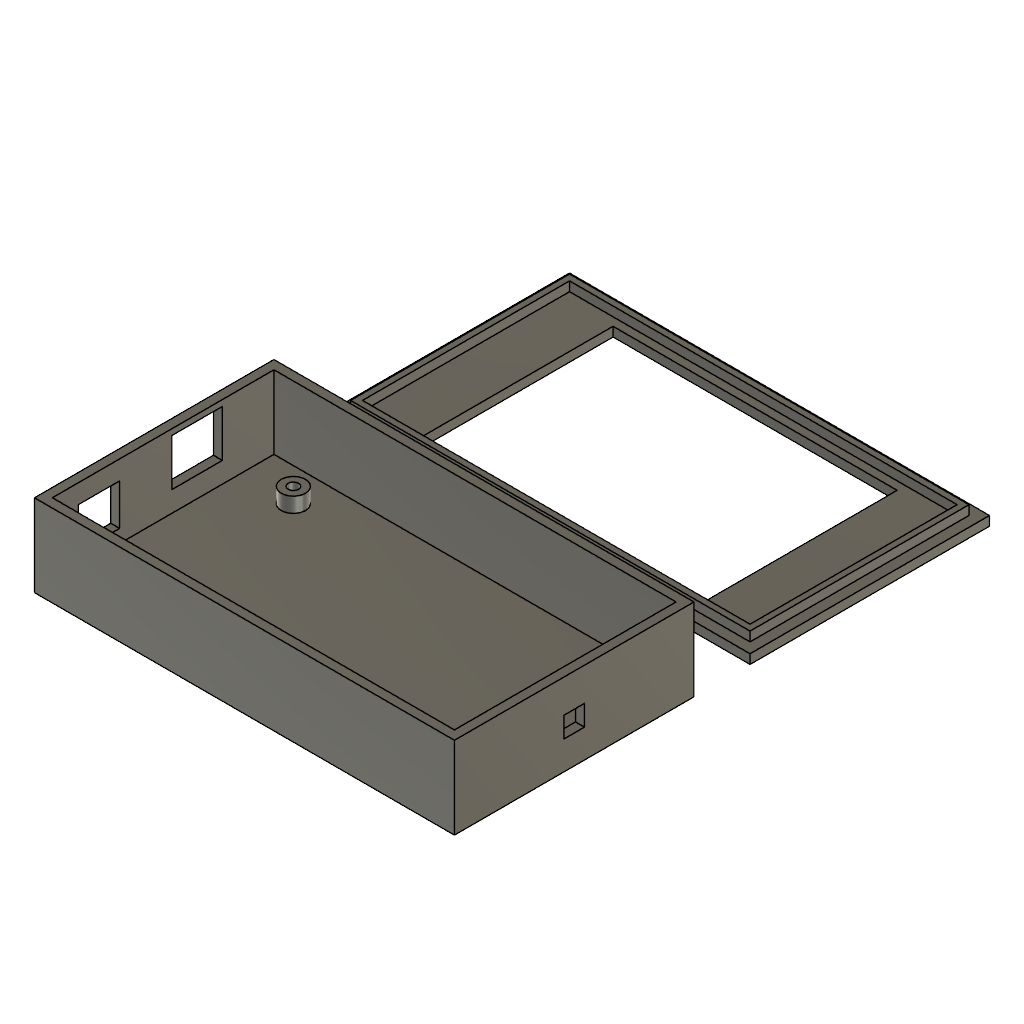
Caja Ardunino Mega (Autodesk Fusion 360 archive; units mm, degrees)
design "Caja Ardunino Mega"
part number: 2026-11-01-23-11-25-753
Autodesk Fusion 360 part; units mm, degrees
sketch "Boceto1" plane through (0, 0, 0) normal (0, 0, 1) x (1, 0, 0)
  line L0 (0, 0) -> (112.4, 0)
  line L1 (112.4, 0) -> (112.4, 64.1)
  line L2 (112.4, 64.1) -> (0, 64.1)
  line L3 (0, 64.1) -> (0, 0)
sketch "Boceto2" plane through (0, 0, 0) normal (0, 0, 1) x (1, 0, 0)
  circle A0 centre (16.4, 4.9) radius 3.25
  circle A1 centre (16.4, 52.9) radius 3.25
  circle A2 centre (97.4, 9.9) radius 3.25
  circle A3 centre (98.9, 37.9) radius 3.25
sketch "Boceto3" plane through (0, 0, 0) normal (0, 0, 1) x (1, 0, 0)
  circle A0 centre (16.4, 4.9) radius 1.4
  circle A1 centre (16.4, 52.9) radius 1.4
  circle A2 centre (97.4, 9.9) radius 1.4
  circle A3 centre (98.9, 37.9) radius 1.4
sketch "Boceto4" plane through (0, 0, 0) normal (1, 0, 0) x (0, 0, -1)
sketch "Boceto5" plane through (0, 0, 0) normal (0, 0, 1) x (1, 0, 0)
  line L0 (0, 0) -> (112.4, 0)
  line L1 (112.4, 0) -> (112.4, 64.1)
  line L2 (112.4, 64.1) -> (0, 64.1)
  line L3 (0, 64.1) -> (0, 0)
sketch "Boceto6" plane through (0, 0, 0) normal (0, 0, 1) x (1, 0, 0)
  circle A0 centre (16.4, 4.9) radius 3.25
  circle A1 centre (16.4, 52.9) radius 3.25
  circle A2 centre (97.4, 9.9) radius 3.25
  circle A3 centre (98.9, 37.9) radius 3.25
sketch "Boceto7" plane through (0, 0, 0) normal (0, 0, 1) x (1, 0, 0)
  circle A0 centre (16.4, 4.9) radius 1.4
  circle A1 centre (16.4, 52.9) radius 1.4
  circle A2 centre (97.4, 9.9) radius 1.4
  circle A3 centre (98.9, 37.9) radius 1.4
sketch "Boceto8" plane through (0, 0, 0) normal (1, 0, 0) x (0, 0, -1)
sketch "Boceto9" plane through (0, 0, 0) normal (0, 0, 1) x (1, 0, 0)
  line L0 (0, 0) -> (112.4, 0)
  line L1 (112.4, 0) -> (112.4, 64.1)
  line L2 (112.4, 64.1) -> (0, 64.1)
  line L3 (0, 64.1) -> (0, 0)
sketch "Boceto10" plane through (0, 0, 0) normal (0, 0, 1) x (1, 0, 0)
  line L0 (2.4, 2.4) -> (110, 2.4)
  line L1 (110, 2.4) -> (110, 61.7)
  line L2 (110, 61.7) -> (2.4, 61.7)
  line L3 (2.4, 61.7) -> (2.4, 2.4)
sketch "Boceto11" plane through (0, 0, 0) normal (0, 0, 1) x (1, 0, 0)
  circle A0 centre (16.4, 4.9) radius 3.25
  circle A1 centre (16.4, 52.9) radius 3.25
  circle A2 centre (97.4, 9.9) radius 3.25
  circle A3 centre (98.9, 37.9) radius 3.25
sketch "Boceto12" plane through (0, 0, 0) normal (0, 0, 1) x (1, 0, 0)
  circle A0 centre (16.4, 4.9) radius 1.4
  circle A1 centre (16.4, 52.9) radius 1.4
  circle A2 centre (97.4, 9.9) radius 1.4
  circle A3 centre (98.9, 37.9) radius 1.4
ref_plane "PlanoDeObra1" through (0, 0, 0) normal (1, 0, 0) x (0, 1, 0)
sketch "Boceto13" plane through (0, 0, 0) normal (1, 0, 0) x (0, 0, -1)
sketch "Boceto14" plane through (0, 0, 0) normal (0, 0, 1) x (1, 0, 0)
  line L0 (0, 0) -> (112.4, 0)
  line L1 (112.4, 0) -> (112.4, 64.1)
  line L2 (112.4, 64.1) -> (0, 64.1)
  line L3 (0, 64.1) -> (0, 0)
sketch "Boceto15" plane through (0, 0, 0) normal (0, 0, 1) x (1, 0, 0)
  line L0 (2.4, 2.4) -> (110, 2.4)
  line L1 (110, 2.4) -> (110, 61.7)
  line L2 (110, 61.7) -> (2.4, 61.7)
  line L3 (2.4, 61.7) -> (2.4, 2.4)
sketch "Boceto16" plane through (0, 0, 0) normal (0, 0, 1) x (1, 0, 0)
  circle A0 centre (16.4, 4.9) radius 3.25
  circle A1 centre (16.4, 52.9) radius 3.25
  circle A2 centre (97.4, 9.9) radius 3.25
  circle A3 centre (98.9, 37.9) radius 3.25
sketch "Boceto17" plane through (0, 0, 0) normal (0, 0, 1) x (1, 0, 0)
  circle A0 centre (16.4, 4.9) radius 1.4
  circle A1 centre (16.4, 52.9) radius 1.4
  circle A2 centre (97.4, 9.9) radius 1.4
  circle A3 centre (98.9, 37.9) radius 1.4
ref_plane "PlanoDeObra2" through (0, 0, 0) normal (1, 0, 0) x (0, 1, 0)
sketch "Boceto18" plane through (0, 0, 0) normal (1, 0, 0) x (0, 0, -1)
sketch "Boceto19" plane through (0, 0, 0) normal (0, 0, 1) x (1, 0, 0)
  line L0 (0, 0) -> (112.4, 0)
  line L1 (112.4, 0) -> (112.4, 64.1)
  line L2 (112.4, 64.1) -> (0, 64.1)
  line L3 (0, 64.1) -> (0, 0)
sketch "Boceto20" plane through (0, 0, 0) normal (0, 0, 1) x (1, 0, 0)
  line L0 (2.4, 2.4) -> (110, 2.4)
  line L1 (110, 2.4) -> (110, 61.7)
  line L2 (110, 61.7) -> (2.4, 61.7)
  line L3 (2.4, 61.7) -> (2.4, 2.4)
sketch "Boceto21" plane through (0, 0, 0) normal (0, 0, 1) x (1, 0, 0)
  circle A0 centre (16.4, 4.9) radius 3.25
  circle A1 centre (16.4, 52.9) radius 3.25
  circle A2 centre (97.4, 9.9) radius 3.25
  circle A3 centre (98.9, 37.9) radius 3.25
sketch "Boceto22" plane through (0, 0, 0) normal (0, 0, 1) x (1, 0, 0)
  circle A0 centre (16.4, 4.9) radius 1.4
  circle A1 centre (16.4, 52.9) radius 1.4
  circle A2 centre (97.4, 9.9) radius 1.4
  circle A3 centre (98.9, 37.9) radius 1.4
ref_plane "PlanoDeObra3" through (0, 0, 0) normal (1, 0, 0) x (0, 1, 0)
sketch "Boceto23" plane through (0, 0, 0) normal (1, 0, 0) x (0, 0, -1)
sketch "Boceto24" plane through (0, 0, 0) normal (0, 0, 1) x (1, 0, 0)
  line L0 (0, 0) -> (112.4, 0)
  line L1 (112.4, 0) -> (112.4, 64.1)
  line L2 (112.4, 64.1) -> (0, 64.1)
  line L3 (0, 64.1) -> (0, 0)
sketch "Boceto25" plane through (0, 0, 0) normal (0, 0, 1) x (1, 0, 0)
  line L0 (2.4, 2.4) -> (110, 2.4)
  line L1 (110, 2.4) -> (110, 61.7)
  line L2 (110, 61.7) -> (2.4, 61.7)
  line L3 (2.4, 61.7) -> (2.4, 2.4)
sketch "Boceto26" plane through (0, 0, 0) normal (0, 0, 1) x (1, 0, 0)
  circle A0 centre (16.4, 4.9) radius 3.25
  circle A1 centre (16.4, 52.9) radius 3.25
  circle A2 centre (97.4, 9.9) radius 3.25
  circle A3 centre (98.9, 37.9) radius 3.25
sketch "Boceto27" plane through (0, 0, 0) normal (0, 0, 1) x (1, 0, 0)
  circle A0 centre (16.4, 4.9) radius 1.4
  circle A1 centre (16.4, 52.9) radius 1.4
  circle A2 centre (97.4, 9.9) radius 1.4
  circle A3 centre (98.9, 37.9) radius 1.4
extrude "Extruir22" cut sketch "Boceto27" along normal blind 4 from surface at 2.4
ref_plane "PlanoDeObra4" through (0, 0, 0) normal (1, 0, 0) x (0, 1, 0)
sketch "Boceto28" plane through (0, 0, 0) normal (1, 0, 0) x (0, 0, -1)
sketch "Boceto29" plane through (0, 0, 0) normal (0, 0, 1) x (1, 0, 0)
  line L0 (0, 0) -> (112.4, 0)
  line L1 (112.4, 0) -> (112.4, 64.1)
  line L2 (112.4, 64.1) -> (0, 64.1)
  line L3 (0, 64.1) -> (0, 0)
sketch "Boceto30" plane through (0, 0, 0) normal (0, 0, 1) x (1, 0, 0)
  line L0 (2.4, 2.4) -> (110, 2.4)
  line L1 (110, 2.4) -> (110, 61.7)
  line L2 (110, 61.7) -> (2.4, 61.7)
  line L3 (2.4, 61.7) -> (2.4, 2.4)
sketch "Boceto31" plane through (0, 0, 0) normal (0, 0, 1) x (1, 0, 0)
  circle A0 centre (16.4, 4.9) radius 3.25
  circle A1 centre (16.4, 52.9) radius 3.25
  circle A2 centre (97.4, 9.9) radius 3.25
  circle A3 centre (98.9, 37.9) radius 3.25
sketch "Boceto32" plane through (0, 0, 0) normal (0, 0, 1) x (1, 0, 0)
  circle A0 centre (16.4, 4.9) radius 1.4
  circle A1 centre (16.4, 52.9) radius 1.4
  circle A2 centre (97.4, 9.9) radius 1.4
  circle A3 centre (98.9, 37.9) radius 1.4
sketch "Boceto33" plane through (0, 0, 0) normal (0, 1, 0) x (1, 0, 0)
  circle A0 centre (0, 11.4) radius 5.5
  line L0 (-0.5, 7.9) -> (1, 7.9)
  line L1 (1, 7.9) -> (1, 20.4)
  line L2 (1, 20.4) -> (-0.5, 20.4)
  line L3 (-0.5, 20.4) -> (-0.5, 7.9)
  circle A1 centre (112.4, 10.4) radius 2.75
sketch "Boceto34" plane through (0, 0, 0) normal (0, 0, 1) x (1, 0, 0)
  line L0 (0, 0) -> (112.4, 0)
  line L1 (112.4, 0) -> (112.4, 64.1)
  line L2 (112.4, 64.1) -> (0, 64.1)
  line L3 (0, 64.1) -> (0, 0)
sketch "Boceto35" plane through (0, 0, 0) normal (0, 0, 1) x (1, 0, 0)
  line L0 (2.4, 2.4) -> (110, 2.4)
  line L1 (110, 2.4) -> (110, 61.7)
  line L2 (110, 61.7) -> (2.4, 61.7)
  line L3 (2.4, 61.7) -> (2.4, 2.4)
sketch "Boceto36" plane through (0, 0, 0) normal (0, 0, 1) x (1, 0, 0)
  circle A0 centre (16.4, 4.9) radius 3.25
  circle A1 centre (16.4, 52.9) radius 3.25
  circle A2 centre (97.4, 9.9) radius 3.25
  circle A3 centre (98.9, 37.9) radius 3.25
sketch "Boceto37" plane through (0, 0, 0) normal (0, 0, 1) x (1, 0, 0)
  circle A0 centre (16.4, 4.9) radius 1.4
  circle A1 centre (16.4, 52.9) radius 1.4
  circle A2 centre (97.4, 9.9) radius 1.4
  circle A3 centre (98.9, 37.9) radius 1.4
sketch "Boceto38" plane through (0, 0, 0) normal (0, 1, 0) x (1, 0, 0)
  circle A0 centre (0, 11.4) radius 5.5
  line L0 (-0.5, 7.9) -> (1, 7.9)
  line L1 (1, 7.9) -> (1, 20.4)
  line L2 (1, 20.4) -> (-0.5, 20.4)
  line L3 (-0.5, 20.4) -> (-0.5, 7.9)
  circle A1 centre (112.4, 10.4) radius 2.75
sketch "Boceto39" plane through (0, 0, 0) normal (0, 0, 1) x (1, 0, 0)
  line L0 (0, 0) -> (112.4, 0)
  line L1 (112.4, 0) -> (112.4, 64.1)
  line L2 (112.4, 64.1) -> (0, 64.1)
  line L3 (0, 64.1) -> (0, 0)
sketch "Boceto40" plane through (0, 0, 0) normal (0, 0, 1) x (1, 0, 0)
  line L0 (2.4, 2.4) -> (110, 2.4)
  line L1 (110, 2.4) -> (110, 61.7)
  line L2 (110, 61.7) -> (2.4, 61.7)
  line L3 (2.4, 61.7) -> (2.4, 2.4)
sketch "Boceto41" plane through (0, 0, 0) normal (0, 0, 1) x (1, 0, 0)
  circle A0 centre (16.4, 4.9) radius 3.25
  circle A1 centre (16.4, 52.9) radius 3.25
  circle A2 centre (97.4, 9.9) radius 3.25
  circle A3 centre (98.9, 37.9) radius 3.25
sketch "Boceto42" plane through (0, 0, 0) normal (0, 0, 1) x (1, 0, 0)
  circle A0 centre (16.4, 4.9) radius 1.4
  circle A1 centre (16.4, 52.9) radius 1.4
  circle A2 centre (97.4, 9.9) radius 1.4
  circle A3 centre (98.9, 37.9) radius 1.4
extrude "Extruir40" cut sketch "Boceto42" along normal blind 4 from surface at 2.4
sketch "Boceto43" plane through (0, 0, 0) normal (0, 0, 1) x (1, 0, 0)
  line L0 (-2, 9.4) -> (4.4, 9.4)
  line L1 (4.4, 9.4) -> (4.4, 20.4)
  line L2 (4.4, 20.4) -> (-2, 20.4)
  line L3 (-2, 20.4) -> (-2, 9.4)
sketch "Boceto44" plane through (0, 0, 0) normal (0, 0, 1) x (1, 0, 0)
  line L0 (-2, 34.4) -> (4.4, 34.4)
  line L1 (4.4, 34.4) -> (4.4, 47.9)
  line L2 (4.4, 47.9) -> (-2, 47.9)
  line L3 (-2, 47.9) -> (-2, 34.4)
sketch "Boceto45" plane through (0, 0, 0) normal (0, 0, 1) x (1, 0, 0)
  line L0 (108, 29.3) -> (114.4, 29.3)
  line L1 (114.4, 29.3) -> (114.4, 34.8)
  line L2 (114.4, 34.8) -> (108, 34.8)
  line L3 (108, 34.8) -> (108, 29.3)
sketch "Boceto46" plane through (0, 0, 0) normal (0, 0, 1) x (1, 0, 0)
  line L0 (0, 0) -> (112.4, 0)
  line L1 (112.4, 0) -> (112.4, 64.1)
  line L2 (112.4, 64.1) -> (0, 64.1)
  line L3 (0, 64.1) -> (0, 0)
sketch "Boceto47" plane through (0, 0, 0) normal (0, 0, 1) x (1, 0, 0)
  line L0 (2.4, 2.4) -> (110, 2.4)
  line L1 (110, 2.4) -> (110, 61.7)
  line L2 (110, 61.7) -> (2.4, 61.7)
  line L3 (2.4, 61.7) -> (2.4, 2.4)
sketch "Boceto48" plane through (0, 0, 0) normal (0, 0, 1) x (1, 0, 0)
  circle A0 centre (16.4, 4.9) radius 3.25
  circle A1 centre (16.4, 52.9) radius 3.25
  circle A2 centre (97.4, 9.9) radius 3.25
  circle A3 centre (98.9, 37.9) radius 3.25
sketch "Boceto49" plane through (0, 0, 0) normal (0, 0, 1) x (1, 0, 0)
  circle A0 centre (16.4, 4.9) radius 1.4
  circle A1 centre (16.4, 52.9) radius 1.4
  circle A2 centre (97.4, 9.9) radius 1.4
  circle A3 centre (98.9, 37.9) radius 1.4
extrude "Extruir47" cut sketch "Boceto49" along normal blind 4 from surface at 2.4
sketch "Boceto50" plane through (0, 0, 0) normal (0, 0, 1) x (1, 0, 0)
  line L0 (-2, 9.4) -> (4.4, 9.4)
  line L1 (4.4, 9.4) -> (4.4, 20.4)
  line L2 (4.4, 20.4) -> (-2, 20.4)
  line L3 (-2, 20.4) -> (-2, 9.4)
sketch "Boceto51" plane through (0, 0, 0) normal (0, 0, 1) x (1, 0, 0)
  line L0 (-2, 34.4) -> (4.4, 34.4)
  line L1 (4.4, 34.4) -> (4.4, 47.9)
  line L2 (4.4, 47.9) -> (-2, 47.9)
  line L3 (-2, 47.9) -> (-2, 34.4)
sketch "Boceto52" plane through (0, 0, 0) normal (0, 0, 1) x (1, 0, 0)
  line L0 (108, 29.3) -> (114.4, 29.3)
  line L1 (114.4, 29.3) -> (114.4, 34.8)
  line L2 (114.4, 34.8) -> (108, 34.8)
  line L3 (108, 34.8) -> (108, 29.3)
sketch "Boceto53" plane through (0, 0, 0) normal (0, 0, 1) x (1, 0, 0)
  line L0 (0, 0) -> (112.4, 0)
  line L1 (112.4, 0) -> (112.4, 64.1)
  line L2 (112.4, 64.1) -> (0, 64.1)
  line L3 (0, 64.1) -> (0, 0)
sketch "Boceto54" plane through (0, 0, 0) normal (0, 0, 1) x (1, 0, 0)
  line L0 (2.75, 2.75) -> (109.65, 2.75)
  line L1 (109.65, 2.75) -> (109.65, 61.35)
  line L2 (109.65, 61.35) -> (2.75, 61.35)
  line L3 (2.75, 61.35) -> (2.75, 2.75)
  line L4 (4.35, 4.35) -> (108.05, 4.35)
  line L5 (108.05, 4.35) -> (108.05, 59.75)
  line L6 (108.05, 59.75) -> (4.35, 59.75)
  line L7 (4.35, 59.75) -> (4.35, 4.35)
sketch "Boceto55" plane through (0, 0, 0) normal (0, 0, 1) x (1, 0, 0)
  line L0 (18.2, 6.55) -> (94.2, 6.55)
  line L1 (94.2, 6.55) -> (94.2, 57.55)
  line L2 (94.2, 57.55) -> (18.2, 57.55)
  line L3 (18.2, 57.55) -> (18.2, 6.55)
sketch "Boceto56" plane through (0, 0, 0) normal (0, 0, 1) x (1, 0, 0)
  line L0 (0, 0) -> (112.4, 0)
  line L1 (112.4, 0) -> (112.4, 64.1)
  line L2 (112.4, 64.1) -> (0, 64.1)
  line L3 (0, 64.1) -> (0, 0)
sketch "Boceto57" plane through (0, 0, 0) normal (0, 0, 1) x (1, 0, 0)
  line L0 (2.75, 2.75) -> (109.65, 2.75)
  line L1 (109.65, 2.75) -> (109.65, 61.35)
  line L2 (109.65, 61.35) -> (2.75, 61.35)
  line L3 (2.75, 61.35) -> (2.75, 2.75)
  line L4 (4.35, 4.35) -> (108.05, 4.35)
  line L5 (108.05, 4.35) -> (108.05, 59.75)
  line L6 (108.05, 59.75) -> (4.35, 59.75)
  line L7 (4.35, 59.75) -> (4.35, 4.35)
sketch "Boceto58" plane through (0, 0, 0) normal (0, 0, 1) x (1, 0, 0)
  line L0 (18.2, 6.55) -> (94.2, 6.55)
  line L1 (94.2, 6.55) -> (94.2, 57.55)
  line L2 (94.2, 57.55) -> (18.2, 57.55)
  line L3 (18.2, 57.55) -> (18.2, 6.55)
sketch "Boceto59" plane through (0, 0, 0) normal (0, 0, 1) x (1, 0, 0)
  line L0 (0, 79.1) -> (112.4, 79.1)
  line L1 (112.4, 79.1) -> (112.4, 143.2)
  line L2 (112.4, 143.2) -> (0, 143.2)
  line L3 (0, 143.2) -> (0, 79.1)
sketch "Boceto60" plane through (0, 0, 0) normal (0, 0, 1) x (1, 0, 0)
  line L0 (2.75, 81.85) -> (109.65, 81.85)
  line L1 (109.65, 81.85) -> (109.65, 140.45)
  line L2 (109.65, 140.45) -> (2.75, 140.45)
  line L3 (2.75, 140.45) -> (2.75, 81.85)
  line L4 (4.35, 83.45) -> (108.05, 83.45)
  line L5 (108.05, 83.45) -> (108.05, 138.85)
  line L6 (108.05, 138.85) -> (4.35, 138.85)
  line L7 (4.35, 138.85) -> (4.35, 83.45)
sketch "Boceto61" plane through (0, 0, 0) normal (0, 0, 1) x (1, 0, 0)
  line L0 (18.2, 85.65) -> (94.2, 85.65)
  line L1 (94.2, 85.65) -> (94.2, 136.65)
  line L2 (94.2, 136.65) -> (18.2, 136.65)
  line L3 (18.2, 136.65) -> (18.2, 85.65)
sketch "Boceto62" plane through (0, 0, 0) normal (0, 0, 1) x (1, 0, 0)
  line L0 (0, 79.1) -> (112.4, 79.1)
  line L1 (112.4, 79.1) -> (112.4, 143.2)
  line L2 (112.4, 143.2) -> (0, 143.2)
  line L3 (0, 143.2) -> (0, 79.1)
sketch "Boceto63" plane through (0, 0, 0) normal (0, 0, 1) x (1, 0, 0)
  line L0 (2.75, 81.85) -> (109.65, 81.85)
  line L1 (109.65, 81.85) -> (109.65, 140.45)
  line L2 (109.65, 140.45) -> (2.75, 140.45)
  line L3 (2.75, 140.45) -> (2.75, 81.85)
  line L4 (4.35, 83.45) -> (108.05, 83.45)
  line L5 (108.05, 83.45) -> (108.05, 138.85)
  line L6 (108.05, 138.85) -> (4.35, 138.85)
  line L7 (4.35, 138.85) -> (4.35, 83.45)
sketch "Boceto64" plane through (0, 0, 0) normal (0, 0, 1) x (1, 0, 0)
  line L0 (18.2, 85.65) -> (94.2, 85.65)
  line L1 (94.2, 85.65) -> (94.2, 136.65)
  line L2 (94.2, 136.65) -> (18.2, 136.65)
  line L3 (18.2, 136.65) -> (18.2, 85.65)
sketch "Boceto65" plane through (0, 0, 0) normal (0, 0, 1) x (1, 0, 0)
  line L0 (0, 0) -> (112.4, 0)
  line L1 (112.4, 0) -> (112.4, 64.1)
  line L2 (112.4, 64.1) -> (0, 64.1)
  line L3 (0, 64.1) -> (0, 0)
extrude "Extruir63" add sketch "Boceto65" along normal blind 22 separate body makes body 1
sketch "Boceto66" plane through (0, 0, 0) normal (0, 0, 1) x (1, 0, 0)
  line L0 (2.4, 2.4) -> (110, 2.4)
  line L1 (110, 2.4) -> (110, 61.7)
  line L2 (110, 61.7) -> (2.4, 61.7)
  line L3 (2.4, 61.7) -> (2.4, 2.4)
extrude "Extruir64" cut sketch "Boceto66" along normal blind 22 from surface at 2.4 bodies 1
sketch "Boceto67" plane through (0, 0, 0) normal (0, 0, 1) x (1, 0, 0)
  circle A0 centre (16.4, 4.9) radius 3.25
  circle A1 centre (16.4, 52.9) radius 3.25
  circle A2 centre (97.4, 9.9) radius 3.25
  circle A3 centre (98.9, 37.9) radius 3.25
extrude "Extruir65" add sketch "Boceto67" along normal blind 4 from surface at 2.4 bodies 1
sketch "Boceto68" plane through (0, 0, 0) normal (0, 0, 1) x (1, 0, 0)
  circle A0 centre (16.4, 4.9) radius 1.4
  circle A1 centre (16.4, 52.9) radius 1.4
  circle A2 centre (97.4, 9.9) radius 1.4
  circle A3 centre (98.9, 37.9) radius 1.4
extrude "Extruir66" cut sketch "Boceto68" along normal blind 4 from surface at 2.4 bodies 1
sketch "Boceto69" plane through (0, 0, 0) normal (0, 0, 1) x (1, 0, 0)
  line L0 (-2, 9.4) -> (4.4, 9.4)
  line L1 (4.4, 9.4) -> (4.4, 20.4)
  line L2 (4.4, 20.4) -> (-2, 20.4)
  line L3 (-2, 20.4) -> (-2, 9.4)
extrude "Extruir67" add sketch "Boceto69" along normal blind 11 from surface at 5.9 separate body makes body 2
sketch "Boceto70" plane through (0, 0, 0) normal (0, 0, 1) x (1, 0, 0)
  line L0 (-2, 34.4) -> (4.4, 34.4)
  line L1 (4.4, 34.4) -> (4.4, 47.9)
  line L2 (4.4, 47.9) -> (-2, 47.9)
  line L3 (-2, 47.9) -> (-2, 34.4)
extrude "Extruir68" add sketch "Boceto70" along normal blind 12.5 from surface at 7.9 separate body makes body 3
sketch "Boceto71" plane through (0, 0, 0) normal (0, 0, 1) x (1, 0, 0)
  line L0 (108, 29.3) -> (114.4, 29.3)
  line L1 (114.4, 29.3) -> (114.4, 34.8)
  line L2 (114.4, 34.8) -> (108, 34.8)
  line L3 (108, 34.8) -> (108, 29.3)
extrude "Extruir69" add sketch "Boceto71" along normal blind 5.5 from surface at 7.65 separate body makes body 4
combine "Combinar5" operation cut target body 1 tool bodies 2 3 4
sketch "Boceto72" plane through (0, 0, 0) normal (0, 0, 1) x (1, 0, 0)
  line L0 (0, 0) -> (112.4, 0)
  line L1 (112.4, 0) -> (112.4, 64.1)
  line L2 (112.4, 64.1) -> (0, 64.1)
  line L3 (0, 64.1) -> (0, 0)
extrude "Extruir70" add sketch "Boceto72" along normal blind 22 separate body makes body 5
sketch "Boceto73" plane through (0, 0, 0) normal (0, 0, 1) x (1, 0, 0)
  line L0 (2.4, 2.4) -> (110, 2.4)
  line L1 (110, 2.4) -> (110, 61.7)
  line L2 (110, 61.7) -> (2.4, 61.7)
  line L3 (2.4, 61.7) -> (2.4, 2.4)
extrude "Extruir71" cut sketch "Boceto73" along normal blind 22 from surface at 2.4 bodies 1 5
sketch "Boceto74" plane through (0, 0, 0) normal (0, 0, 1) x (1, 0, 0)
  circle A0 centre (16.4, 4.9) radius 3.25
  circle A1 centre (16.4, 52.9) radius 3.25
  circle A2 centre (97.4, 9.9) radius 3.25
  circle A3 centre (98.9, 37.9) radius 3.25
extrude "Extruir72" add sketch "Boceto74" along normal blind 4 from surface at 2.4 bodies 1 5
sketch "Boceto75" plane through (0, 0, 0) normal (0, 0, 1) x (1, 0, 0)
  circle A0 centre (16.4, 4.9) radius 1.4
  circle A1 centre (16.4, 52.9) radius 1.4
  circle A2 centre (97.4, 9.9) radius 1.4
  circle A3 centre (98.9, 37.9) radius 1.4
extrude "Extruir73" cut sketch "Boceto75" along normal blind 4 from surface at 2.4 bodies 1
sketch "Boceto76" plane through (0, 0, 0) normal (0, 0, 1) x (1, 0, 0)
  line L0 (-2, 9.4) -> (4.4, 9.4)
  line L1 (4.4, 9.4) -> (4.4, 20.4)
  line L2 (4.4, 20.4) -> (-2, 20.4)
  line L3 (-2, 20.4) -> (-2, 9.4)
extrude "Extruir74" add sketch "Boceto76" along normal blind 11 from surface at 5.9 separate body makes body 6
sketch "Boceto77" plane through (0, 0, 0) normal (0, 0, 1) x (1, 0, 0)
  line L0 (-2, 34.4) -> (4.4, 34.4)
  line L1 (4.4, 34.4) -> (4.4, 47.9)
  line L2 (4.4, 47.9) -> (-2, 47.9)
  line L3 (-2, 47.9) -> (-2, 34.4)
extrude "Extruir75" add sketch "Boceto77" along normal blind 12.5 from surface at 7.9 separate body makes body 7
sketch "Boceto78" plane through (0, 0, 0) normal (0, 0, 1) x (1, 0, 0)
  line L0 (108, 29.3) -> (114.4, 29.3)
  line L1 (114.4, 29.3) -> (114.4, 34.8)
  line L2 (114.4, 34.8) -> (108, 34.8)
  line L3 (108, 34.8) -> (108, 29.3)
extrude "Extruir76" add sketch "Boceto78" along normal blind 5.5 from surface at 7.65 separate body makes body 8
combine "Combinar6" operation cut target body 1 tool bodies 6 7 8
sketch "Boceto79" plane through (0, 0, 0) normal (0, 0, 1) x (1, 0, 0)
  line L0 (0, 79.1) -> (112.4, 79.1)
  line L1 (112.4, 79.1) -> (112.4, 143.2)
  line L2 (112.4, 143.2) -> (0, 143.2)
  line L3 (0, 143.2) -> (0, 79.1)
extrude "Extruir77" add sketch "Boceto79" along normal blind 2.5 separate body makes body 9
sketch "Boceto80" plane through (0, 0, 0) normal (0, 0, 1) x (1, 0, 0)
  line L0 (2.75, 81.85) -> (109.65, 81.85)
  line L1 (109.65, 81.85) -> (109.65, 140.45)
  line L2 (109.65, 140.45) -> (2.75, 140.45)
  line L3 (2.75, 140.45) -> (2.75, 81.85)
  line L4 (4.35, 83.45) -> (108.05, 83.45)
  line L5 (108.05, 83.45) -> (108.05, 138.85)
  line L6 (108.05, 138.85) -> (4.35, 138.85)
  line L7 (4.35, 138.85) -> (4.35, 83.45)
extrude "Extruir78" add sketch "Boceto80" along normal blind 2.5 from surface at 2.5 bodies 9
sketch "Boceto81" plane through (0, 0, 0) normal (0, 0, 1) x (1, 0, 0)
  line L0 (18.2, 85.65) -> (94.2, 85.65)
  line L1 (94.2, 85.65) -> (94.2, 136.65)
  line L2 (94.2, 136.65) -> (18.2, 136.65)
  line L3 (18.2, 136.65) -> (18.2, 85.65)
extrude "Extruir79" cut sketch "Boceto81" along normal blind 7 from surface at -1 bodies 9
sketch "Boceto82" plane through (0, 0, 0) normal (0, 0, 1) x (1, 0, 0)
  line L0 (0, 79.1) -> (112.4, 79.1)
  line L1 (112.4, 79.1) -> (112.4, 143.2)
  line L2 (112.4, 143.2) -> (0, 143.2)
  line L3 (0, 143.2) -> (0, 79.1)
extrude "Extruir80" add sketch "Boceto82" along normal blind 2.5 separate body makes body 10
sketch "Boceto83" plane through (0, 0, 0) normal (0, 0, 1) x (1, 0, 0)
  line L0 (2.75, 81.85) -> (109.65, 81.85)
  line L1 (109.65, 81.85) -> (109.65, 140.45)
  line L2 (109.65, 140.45) -> (2.75, 140.45)
  line L3 (2.75, 140.45) -> (2.75, 81.85)
  line L4 (4.35, 83.45) -> (108.05, 83.45)
  line L5 (108.05, 83.45) -> (108.05, 138.85)
  line L6 (108.05, 138.85) -> (4.35, 138.85)
  line L7 (4.35, 138.85) -> (4.35, 83.45)
extrude "Extruir81" add sketch "Boceto83" along normal blind 2.5 from surface at 2.5 bodies 9 10
sketch "Boceto84" plane through (0, 0, 0) normal (0, 0, 1) x (1, 0, 0)
  line L0 (18.2, 85.65) -> (94.2, 85.65)
  line L1 (94.2, 85.65) -> (94.2, 136.65)
  line L2 (94.2, 136.65) -> (18.2, 136.65)
  line L3 (18.2, 136.65) -> (18.2, 85.65)
extrude "Extruir82" cut sketch "Boceto84" along normal blind 7 from surface at -1 bodies 9
equation "wall = 2.4 mm"
equation "clearance = 0.4 mm"
equation "mega_L = 101.6 mm"
equation "mega_W = 53.3 mm"
equation "box_L = mega_L + 6 mm"
equation "box_W = mega_W + 6 mm"
equation "box_H = 22 mm"
equation "standoff_H = 4 mm"
